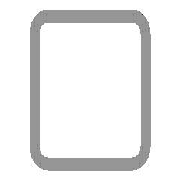
# Autodesk Inventor part: DIN EN 10219-2 - 90 x 90 x 5  - 120
Saved by Autodesk Inventor 2025.3 (Build 293356000, 356)
## iProperties
IsCustomPart: 1
Created: 2024-01-20
Part Number: DIN EN 10219-2 - 90 x 90 x 5  - 120
Material: Stahl, weich
Description: Kaltgeformte, geschweißte Baustahl-Hohlprofile aus unlegiertem Feinkorn-Baustahl
Document SubType Name: Modeling
Standard: DIN EN 10219-2
Designer: trist
Standard Revision: 2006-07
Standards Organization: DIN
Language: de-DE
Size Designation: 90 x 90 x 5  - 120
Categories: <MemberInstance><Categories><Category DisplayName="Profile" InternalName="089c4875-fa83-4c05-b084-43b9cc11f5ed" Mnemonic="GRDR"><CategoryParameter DisplayName="Masse pro Längeneinheit" InternalName="0bb95a10-148f-4027-a459-38d7b056702a" Mnemonic="shpmass"/><CategoryParameter DisplayName="Querschnittsfläche" InternalName="1ff91680-64b0-4202-b9a3-7fd3f94bba3b" Mnemonic="secarea"/><CategoryParameter DisplayName="Trägheitsradius (x)" InternalName="25778675-03e9-40c1-b6a8-4a9ed693320d" Mnemonic="gyrradx"/><CategoryParameter DisplayName="Torsion-Festigkeitsmodul" InternalName="26c1ec35-5026-4c63-ad0a-751cf684a536" Mnemonic="torrigmod"/><CategoryParameter DisplayName="Abstand zum Schwerpunkt X-X" InternalName="26c9bdb8-9c79-4b4f-a92e-8e197583c9c4" Mnemonic="grcendistX"/><CategoryParameter DisplayName="Alte Varianten-ID" InternalName="340afe4f-75d7-48d3-ab7d-943f3c3da468" Mnemonic="LegacyMemberID"/><CategoryParameter DisplayName="Basislänge" InternalName="42e34263-8f20-4d0e-ad48-bf1385b87c24" Mnemonic="shplen"/><CategoryParameter DisplayName="Trägheitsmoment (y)" InternalName="4b9f58ea-bced-460e-81ea-3d29ca5a49e3" Mnemonic="inermomy"/><CategoryParameter DisplayName="Trägheitsmoment (x)" InternalName="4cd780bc-73d7-43ac-917a-579e5cbd684d" Mnemonic="inermomx"/><CategoryParameter DisplayName="Benutzerdefinierter Basispunkt" InternalName="4f1d1b73-316d-484b-a3df-9cbabb16eb77" Mnemonic="shpBasePoint"/><CategoryParameter DisplayName="Objekthöhe" InternalName="50274e7d-5ac0-4796-92cb-c59e54983c67" Mnemonic="shpheig"/><CategoryParameter DisplayName="Widerstandsmoment (y)" InternalName="59eaa5e9-d227-48dc-b6c1-6920f96e0f95" Mnemonic="secmody"/><CategoryParameter DisplayName="Schnittbezeichnung" InternalName="5a64d034-428d-49c8-ba32-7619764de20f" Mnemonic="shpdes"/><CategoryParameter DisplayName="Widerstandsmoment (x)" InternalName="72cfad18-cf51-4ed4-aaa7-c6b224f8419f" Mnemonic="secmodx"/><CategoryParameter DisplayName="Drehrissmodul" InternalName="7c55a8dc-8844-49f9-a867-cc677b30ec9a" Mnemonic="torsecmod"/><CategoryParameter DisplayName="Objektbreite" InternalName="7c717d54-a18f-4666-b4d4-573cce22c62c" Mnemonic="shpwdth"/><CategoryParameter DisplayName="Zweite Objektdicke" InternalName="9251a8e1-85fd-4e47-af99-afdb762317d9" Mnemonic="shpthick2"/><CategoryParameter DisplayName="GG Erstellt" InternalName="9c666724-f362-4ea7-ac62-f6a007de5c69" Mnemonic="shpFGAuto"/><CategoryParameter DisplayName="Abstand zum Schwerpunkt Y-Y" InternalName="bcc4fb17-7af4-436a-8f8c-d0aa3b0248c5" Mnemonic="grcendistY"/><CategoryParameter DisplayName="Trägheitsradius (y)" InternalName="bfa18ebe-1636-4dbe-8d42-b263e0b73184" Mnemonic="gyrrady"/><CategoryParameter DisplayName="Objektdicke" InternalName="d109cf76-8eb4-42fc-9800-4409734adc67" Mnemonic="shpthick"/><CategoryParameter DisplayName="Koeffizient für Schubverschiebung" InternalName="de4c90c6-aaa8-468f-a335-6737b311b5d3" Mnemonic="shdispc"/><Category DisplayName="Vierkantrohre (quadratisch/rechteckig)" InternalName="afc8e2d8-05d6-4609-8807-f98a9b7d2ed0" Mnemonic="SQRSHP"><CategoryParameter DisplayName="Querschnittsfläche" InternalName="2f7f79dd-983c-4263-802a-5b6a1495fdc5" Mnemonic="secarea"/><CategoryParameter DisplayName="Widerstandsmoment (x)" InternalName="50d965a6-04bf-46b9-8ace-861858d348e6" Mnemonic="secmodx"/><CategoryParameter DisplayName="Widerstandsmoment (y)" InternalName="5106aeac-54a2-4159-a9af-8933dd39dba2" Mnemonic="secmody"/><CategoryParameter DisplayName="Objektdicke" InternalName="52712fc5-f4ee-4eda-b3f2-6fce82c26419" Mnemonic="shpthick"/><CategoryParameter DisplayName="Trägheitsmoment (y)" InternalName="55ec8510-8276-4c45-8f10-594e0fee7eb3" Mnemonic="inermomy"/><CategoryParameter DisplayName="Trägheitsradius (x)" InternalName="56c89926-a299-4389-a862-ac94c9691272" Mnemonic="gyrradx"/><CategoryParameter DisplayName="Radius" InternalName="5d8d062c-e28e-41c1-98da-8e5fee36da1a" Mnemonic="shprad"/><CategoryParameter DisplayName="Trägheitsmoment (x)" InternalName="8c4637b6-6b69-4878-9d5d-26a32185d655" Mnemonic="inermomx"/><CategoryParameter DisplayName="Objektbreite" InternalName="8c8a1782-5e80-4d77-858b-304b1c0ad1fd" Mnemonic="shpwdth"/><CategoryParameter DisplayName="Trägheitsradius (y)" InternalName="fa48a7f5-f030-40f9-a60b-de8a845b7104" Mnemonic="gyrrady"/></Category></Category><Category DisplayName="Datentyp" InternalName="23b78d0f-2648-40c6-8793-ca6db495c9e8" Mnemonic="DATATYPE"><CategoryParameter DisplayName="Anzeigename" InternalName="05415f3d-3907-474b-a020-eb9d644f4cf3" Mnemonic="DISPLAYNAME"/><CategoryParameter DisplayName="Norm" InternalName="0c0a119c-1e12-4c84-803f-101930972f5e" Mnemonic="STANDARD"/><CategoryParameter DisplayName="Beschreibung" InternalName="13903e3d-64b1-4950-80da-f627842ea37f" Mnemonic="DESCRIPTION"/><CategoryParameter DisplayName="Bezeichnung" InternalName="2675968c-4ce5-49e0-a4f5-552d29089031" Mnemonic="DESIGNATION"/><CategoryParameter DisplayName="Standardzeile" InternalName="2af9ec52-faaa-4026-b378-f9fa4afca842" Mnemonic="DEFAULTROW"/><CategoryParameter DisplayName="Ordnername" InternalName="3f06958e-8713-4116-9be7-ed6184ecc97b" Mnemonic="FOLDERNAME"/><CategoryParameter DisplayName="Revisionsanleitung" InternalName="45a75005-10b1-4dfc-8d6d-dfe629f0b93c" Mnemonic="REVISIONGUID"/><CategoryParameter DisplayName="Dateiname" InternalName="8b46a4cc-9585-4fed-90c3-899f57e09a73" Mnemonic="FILENAME"/><CategoryParameter DisplayName="Normungsorganisation" InternalName="8f5914e1-4693-403f-8ab5-d37768198c9d" Mnemonic="STDSORG"/><CategoryParameter DisplayName="Gruppenversion" InternalName="914462f6-6e19-4b14-ba84-155b9680b1d0" Mnemonic="FAMILYREVISION"/><CategoryParameter DisplayName="Normrevision" InternalName="91d5a463-65c2-4fde-b823-3b7fea5e8e17" Mnemonic="STANDARDREVISION"/><CategoryParameter DisplayName="Variantenrevision" InternalName="a65d44b9-392f-4f4f-857b-e4b3d54996fe" Mnemonic="MEMBERREVISION"/><CategoryParameter DisplayName="ClipFormat" InternalName="bc51e27b-3422-4e78-93ef-cec197ddf230" Mnemonic="CLIPFORMAT"/><CategoryParameter DisplayName="Hersteller" InternalName="cd6c7a72-a28a-4e50-99a9-2c7f4e13e5ad" Mnemonic="MANUFACTURER"/><CategoryParameter DisplayName="InternerName" InternalName="cf1d0246-76d9-4b4a-8305-fa0409afb5c1" Mnemonic="INTERNALNAME"/><CategoryParameter DisplayName="IstMetrisch" InternalName="e2385c5b-1ea4-4823-96a8-8de651266ec3" Mnemonic="ISMETRIC"/><Category DisplayName="Bauteil" InternalName="c0e0b642-3bcb-4cc8-9e80-f96d35c4afa4" Mnemonic="PART"><CategoryParameter DisplayName="Bauteilnummer" InternalName="016b6077-bfbe-49bd-92c9-d8d59c39c941" Mnemonic="PARTNUMBER"/><CategoryParameter DisplayName="Bestandsnummer" InternalName="4dba7c1c-e26c-444e-836c-b08b433409a8" Mnemonic="STOCKNUMBER"/><CategoryParameter DisplayName="Materialschlüssel" InternalName="5c9a8adb-dd2b-4535-b97f-0a94a95fe41f" Mnemonic="MATERIALKEY"/><CategoryParameter DisplayName="Material" InternalName="818a152a-d3c3-49ca-80ee-df7d91421b8e" Mnemonic="MATERIAL"/></Category></Category><Category DisplayName="ÄltereVersionenzuweisen" InternalName="cd87c42b-3e48-431e-b5c0-1cbeb14dfe77" Mnemonic="LEGACYMAP"><CategoryParameter DisplayName="Eindeutige DA-Varianten-ID" InternalName="0918ad47-427f-4fed-ae26-24c81c58f590" Mnemonic="DACOOKIE"/><CategoryParameter DisplayName="ID zusammenführen" InternalName="0ee8fb18-e2ed-4f39-96f6-1f4b5f50aa71" Mnemonic="MERGE11"/><CategoryParameter DisplayName="Eindeutige CC-Varianten-ID" InternalName="5193edd4-b2b0-4ab4-9d54-de900eee34e0" Mnemonic="CCCOOKIE"/><CategoryParameter DisplayName="ID aufteilen" InternalName="72b5c83c-be7f-45c4-ae51-9160ea6deb26" Mnemonic="SPLIT"/><CategoryParameter DisplayName="VarianteID" InternalName="8e5e0294-fc51-4c8f-b3d7-003dc5ed94f6" Mnemonic="MEMBERID"/><CategoryParameter DisplayName="Katalogname" InternalName="d99d1e27-aa94-4de2-af4c-c348882a6f4f" Mnemonic="CATALOGNAME"/><CategoryParameter DisplayName="Gruppennummer" InternalName="e705e1f4-09cb-413e-91f9-551b4188271e" Mnemonic="FAMILYNUMBER"/></Category></Categories><FamilyTemplate Id="gp0601"><FamilyTemplateParameters><FamilyTemplateParameter ObjectType="kUserParameterObject" ValueType="xs:double" Id="1" ObjectReferenceKey="G_H"/><FamilyTemplateParameter ObjectType="kUserParameterObject" ValueType="xs:double" Id="2" ObjectReferenceKey="B_L"/><FamilyTemplateParameter ObjectType="kUserParameterObject" ValueType="xs:double" Id="6" ObjectReferenceKey="G_W"/><FamilyTemplateParameter ObjectType="kUserParameterObject" ValueType="xs:double" Id="7" ObjectReferenceKey="G_T"/><FamilyTemplateParameter ObjectType="kUserParameterObject" ValueType="xs:double" Id="8" ObjectReferenceKey="G_IR"/><FamilyTemplateParameter ObjectType="kPropertyObject" ValueType="xs:string" Id="100" ObjectReferenceKey="{32853F0F-3444-11d1-9E93-0060B03C1CA6}" SubObjectId="52"/><FamilyTemplateParameter ObjectType="kPropertyObject" ValueType="xs:string" Id="105" ObjectReferenceKey="{32853F0F-3444-11d1-9E93-0060B03C1CA6}" SubObjectId="5"/><FamilyTemplateParameter ObjectType="kPartComponentDefinitionObject" ValueType="xs:string" Id="110" SubObjectId="Material"/><FamilyTemplateParameter ObjectType="kPropertyObject" ValueType="xs:string" Id="112" ObjectReferenceKey="{32853F0F-3444-11d1-9E93-0060B03C1CA6}" SubObjectId="55"/></FamilyTemplateParameters></FamilyTemplate><CategoryParameterMap><ParamToTemplateMap><ParamToTemplate CategoryParameter="//CategoryParameter[@InternalName='05415f3d-3907-474b-a020-eb9d644f4cf3']" ConstantValue="DIN EN 10219-2 (Square Hollow Section - Cold Formed)"/><ParamToTemplate CategoryParameter="//CategoryParameter[@InternalName='cf1d0246-76d9-4b4a-8305-fa0409afb5c1']" ConstantValue="f4eb4807-7530-48bf-9740-f5a60eee53a8"/><ParamToTemplate CategoryParameter="//CategoryParameter[@InternalName='3f06958e-8713-4116-9be7-ed6184ecc97b']" ConstantValue="DIN EN 10219-2(1)"/><ParamToTemplate CategoryParameter="//CategoryParameter[@InternalName='914462f6-6e19-4b14-ba84-155b9680b1d0']" ConstantValue="10"/><ParamToTemplate CategoryParameter="//CategoryParameter[@InternalName='bc51e27b-3422-4e78-93ef-cec197ddf230']" ConstantValue="CF_INVENTOR.STDPARTS"/><ParamToTemplate CategoryParameter="//CategoryParameter[@InternalName='e2385c5b-1ea4-4823-96a8-8de651266ec3']" ConstantValue="true"/><ParamToTemplate CategoryParameter="//CategoryParameter[@InternalName='13903e3d-64b1-4950-80da-f627842ea37f']" ConstantValue="Cold formed welded structural hollow sections of non-alloy and fine grain structural steel"/><ParamToTemplate CategoryParameter="//CategoryParameter[@InternalName='8f5914e1-4693-403f-8ab5-d37768198c9d']" ConstantValue="DIN"/><ParamToTemplate CategoryParameter="//CategoryParameter[@InternalName='0c0a119c-1e12-4c84-803f-101930972f5e']" ConstantValue="DIN EN 10219-2"/><ParamToTemplate CategoryParameter="//CategoryParameter[@InternalName='cd6c7a72-a28a-4e50-99a9-2c7f4e13e5ad']" TemplateParameter="104"/><ParamToTemplate CategoryParameter="//CategoryParameter[@InternalName='91d5a463-65c2-4fde-b823-3b7fea5e8e17']" ConstantValue="2006-07"/><ParamToTemplate CategoryParameter="//CategoryParameter[@InternalName='45a75005-10b1-4dfc-8d6d-dfe629f0b93c']" ConstantValue="fa0180ad-9900-4c48-9c99-ee51de72b725"/><ParamToTemplate CategoryParameter="//CategoryParameter[@InternalName='2af9ec52-faaa-4026-b378-f9fa4afca842']" ConstantValue="1"/><ParamToTemplate CategoryParameter="//CategoryParameter[@InternalName='9c666724-f362-4ea7-ac62-f6a007de5c69']" ConstantValue="1"/><ParamToTemplate CategoryParameter="//CategoryParameter[@InternalName='d99d1e27-aa94-4de2-af4c-c348882a6f4f']" ConstantValue="BSI"/><ParamToTemplate CategoryParameter="//CategoryParameter[@InternalName='e705e1f4-09cb-413e-91f9-551b4188271e']" ConstantValue="158"/><ParamToTemplate CategoryParameter="//CategoryParameter[@InternalName='8b46a4cc-9585-4fed-90c3-899f57e09a73']" ConstantValue="DIN EN 10219-2 - 90 x 90 x 5  - 120"/><ParamToTemplate CategoryParameter="//CategoryParameter[@InternalName='a65d44b9-392f-4f4f-857b-e4b3d54996fe']" ConstantValue="49229FD5-5431-4EE6-B6F3-2C28CB392A87"/><ParamToTemplate CategoryParameter="//CategoryParameter[@InternalName='8c4637b6-6b69-4878-9d5d-26a32185d655']" ConstantValue="193"/><ParamToTemplate CategoryParameter="//CategoryParameter[@InternalName='56c89926-a299-4389-a862-ac94c9691272']" ConstantValue="34,3"/><ParamToTemplate CategoryParameter="//CategoryParameter[@InternalName='50d965a6-04bf-46b9-8ace-861858d348e6']" ConstantValue="42,9"/><ParamToTemplate CategoryParameter="//CategoryParameter[@InternalName='2f7f79dd-983c-4263-802a-5b6a1495fdc5']" ConstantValue="16,4"/><ParamToTemplate CategoryParameter="//CategoryParameter[@InternalName='7c55a8dc-8844-49f9-a867-cc677b30ec9a']" ConstantValue="64,7"/><ParamToTemplate CategoryParameter="//CategoryParameter[@InternalName='26c1ec35-5026-4c63-ad0a-751cf684a536']" ConstantValue="316"/><ParamToTemplate CategoryParameter="//CategoryParameter[@InternalName='de4c90c6-aaa8-468f-a335-6737b311b5d3']" ConstantValue="2,1962593"/><ParamToTemplate CategoryParameter="//CategoryParameter[@InternalName='5a64d034-428d-49c8-ba32-7619764de20f']" ConstantValue="90 x 90 x 5"/><ParamToTemplate CategoryParameter="//CategoryParameter[@InternalName='8e5e0294-fc51-4c8f-b3d7-003dc5ed94f6']" ConstantValue="38"/><ParamToTemplate CategoryParameter="//CategoryParameter[@InternalName='42e34263-8f20-4d0e-ad48-bf1385b87c24']" TemplateParameter="2"/><ParamToTemplate CategoryParameter="//CategoryParameter[@InternalName='2675968c-4ce5-49e0-a4f5-552d29089031']" TemplateParameter="100"/><ParamToTemplate CategoryParameter="//CategoryParameter[@InternalName='50274e7d-5ac0-4796-92cb-c59e54983c67']" TemplateParameter="1"/><ParamToTemplate CategoryParameter="//CategoryParameter[@InternalName='52712fc5-f4ee-4eda-b3f2-6fce82c26419']" TemplateParameter="7"/><ParamToTemplate CategoryParameter="//CategoryParameter[@InternalName='8c8a1782-5e80-4d77-858b-304b1c0ad1fd']" TemplateParameter="6"/><ParamToTemplate CategoryParameter="//CategoryParameter[@InternalName='818a152a-d3c3-49ca-80ee-df7d91421b8e']" TemplateParameter="110"/><ParamToTemplate CategoryParameter="//CategoryParameter[@InternalName='016b6077-bfbe-49bd-92c9-d8d59c39c941']" TemplateParameter="105"/><ParamToTemplate CategoryParameter="//CategoryParameter[@InternalName='4dba7c1c-e26c-444e-836c-b08b433409a8']" TemplateParameter="112"/></ParamToTemplateMap></CategoryParameterMap></MemberInstance>
Stock Number: 90 x 90 x 5
Mass: 1529.59 g
Surface Area: 812.069 cm^2
Volume: 194.852 cm^3
Density: 7.85 g/cm^3
Appearance: Halbpoliert
G_L: 120,000 mm
Author: trist
Autodesk Inventor part; units mm, degrees
ref_plane "YZ Plane" through (0, 0, 0) normal (1, 0, 0) x (0, 1, 0)
ref_plane "Startebene" through (0, 0, 0) normal (0, 0, 1) x (1, 0, 0)
ref_plane "Endebene" through (0, 0, 120) normal (0, 0, 1) x (1, 0, 0)
sketch "Skizze" plane through (0, 0, 0) normal (0, 0, 1) x (1, 0, 0)
  line L0 (-45, -35) -> (-45, 35)
  line L1 (-35, 45) -> (35, 45)
  line L2 (45, 35) -> (45, -35)
  line L3 (35, -45) -> (-35, -45)
  arc A0 (-45, -35) -> (-35, -45) centre (-35, -35) ccw
  arc A1 (-35, 45) -> (-45, 35) centre (-35, 35) ccw
  arc A2 (45, 35) -> (35, 45) centre (35, 35) ccw
  arc A3 (35, -45) -> (45, -35) centre (35, -35) ccw
  arc A4 (-35, 40) -> (-40, 35) centre (-35, 35) ccw
  line L4 (-35, 40) -> (35, 40)
  arc A5 (40, 35) -> (35, 40) centre (35, 35) ccw
  line L5 (40, 35) -> (40, -35)
  arc A6 (35, -40) -> (40, -35) centre (35, -35) ccw
  line L6 (35, -40) -> (-35, -40)
  arc A7 (-40, -35) -> (-35, -40) centre (-35, -35) ccw
  line L7 (-40, -35) -> (-40, 35)
  line L8 (0, 65.8995) -> (0, -65.8995) construction
  line L9 (-65.8995, 0) -> (65.8995, 0) construction
  dimension "d7" = 10
  dimension "d10" = 90
  dimension "d11" = 90
  dimension "d12" = 5
  dimension "d15" = 45
  dimension "d16" = 45
  constraints: 16 end point, 16 point on circle, 8 centre point, 8 tangent, 4 parallel, 3 equal radius, 2 perpendicular, 7 other
  measures "d7" radius of A0
  measures "d10" distance between parallel lines of L1 L3
  measures "d11" distance between parallel lines of L0 L2
  measures "d12" distance between parallel lines of L2 L5
  measures "d15" distance between parallel lines of L1 L9
  measures "d16" distance between parallel lines of L8 L2
extrude "Körper" add sketch "Skizze" along normal up to surface (120 mm away) from surface at 0
sketch "Sketch3" plane through (0, 0, 0) normal (0, 0, 1) x (1, 0, 0)
  line L0 (0, 0) -> (10, 0)
ref_plane "Work Plane3" through (0, 0, 0) normal (0, -1, 0) x (1, 0, 0)
sketch "Skizze5" plane through (-35, -45, 0) normal (0, -1, 0) x (1, 0, 0)
  line L0 (18, 62) -> (63, 62)
  line L1 (63, 62) -> (63, 120)
  line L2 (63, 120) -> (18, 120)
  line L3 (18, 120) -> (18, 62)
  line L4 (70, 120) -> (0, 120) projected
  line L5 (0, 120) -> (70, 120)
  line L6 (70, 0) -> (70, 120) projected
  line L7 (0, 0) -> (0, 120) projected
  point P0 (35, 0)
  point P1 (35, 120)
  dimension "d19" = 58
  dimension "d20" = 0
  dimension "d21" = 45
  dimension "d99" = 63
  constraints: 10 end point, 2 horizontal, 2 parallel, 1 midpoint, 1 perpendicular
  measures "d19" distance between parallel lines of L0 L4
  measures "d20" distance between parallel lines of L4 L2
  measures "d21" distance between parallel lines of L1 L3
  measures "d99" distance between parallel lines of L1 L7
extrude "Extrusion2" cut sketch "Skizze5" against normal blind 10
sketch "Skizze6" plane through (0, 0, 0) normal (0, 0, -1) x (-1, 0, 0)
  line L0 (63, 0) -> (-63, 0) projected
  line L1 (0, -63) -> (0, 63) projected
  line L2 (-40, -35) -> (-40, 35) projected
  line L3 (-35, 40) -> (35, 40) projected
  line L4 (40, 35) -> (40, -35) projected
  line L5 (35, -40) -> (-35, -40) projected
  circle A0 centre (-31.82, 31.82) radius 3
  circle A1 centre (-31.82, -31.82) radius 3
  circle A2 centre (31.82, -31.82) radius 3
  circle A3 centre (31.82, 31.82) radius 3
  line L6 (-40, 40) -> (-26, 40)
  line L7 (-26, 40) -> (-26, 26)
  line L8 (-26, 26) -> (-40, 26)
  line L9 (-40, 26) -> (-40, 40)
  line L10 (-40, -40) -> (-26, -40)
  line L11 (-26, -40) -> (-26, -26)
  line L12 (-26, -26) -> (-40, -26)
  line L13 (-40, -26) -> (-40, -40)
  line L14 (40, -40) -> (26, -40)
  line L15 (26, -40) -> (26, -26)
  line L16 (26, -26) -> (40, -26)
  line L17 (40, -26) -> (40, -40)
  line L18 (40, 40) -> (26, 40)
  line L19 (26, 40) -> (26, 26)
  line L20 (26, 26) -> (40, 26)
  line L21 (40, 26) -> (40, 40)
  point P0 (0, 0)
  point P1 (-28, -26)
  point P2 (-26, -28)
  point P3 (-28, 26)
  point P4 (-26, 28)
  point P5 (26, 28)
  point P6 (28, 26)
  point P7 (26, -28)
  point P8 (28, -26)
  point P9 (-35, -40)
  dimension "d110" = 6
  dimension "d28" = 6
  dimension "d29" = 6
  dimension "d30" = 6
  dimension "d31" = 6
  dimension "d32" = 63.64
  dimension "d33" = 63.64
  dimension "d34" = 63.64
  dimension "d36" = 63.64
  dimension "d37" = 8.18
  dimension "d38" = 8.18
  dimension "d39" = 8.18
  dimension "d40" = 8.18
  dimension "d41" = 14
  dimension "d42" = 14
  dimension "d43" = 14
  dimension "d44" = 14
  dimension "d45" = 14
  dimension "d46" = 14
  dimension "d47" = 14
  dimension "d48" = 14
  dimension "d49" = 52
  dimension "d50" = 52
  dimension "d51" = 52
  dimension "d52" = 52
  dimension "d54" = 2
  dimension "d55" = 2
  dimension "d56" = 2
  dimension "d57" = 2
  dimension "d58" = 2
  dimension "d59" = 2
  dimension "d60" = 2
  dimension "d61" = 2
  constraints: 32 end point, 10 point on line, 8 parallel, 4 centre point, 4 horizontal, 4 perpendicular, 2 other
  measures "d28" diameter of A1
  measures "d29" diameter of A2
  measures "d30" diameter of A3
  measures "d31" diameter of A0
  measures "d32" distance of A3.centre A0.centre
  measures "d33" distance of A1.centre A0.centre
  measures "d34" distance of A2.centre A1.centre
  measures "d36" distance of A2.centre A3.centre
  measures "d37" distance from line of L3 A0.centre
  measures "d38" distance from line of L2 A1.centre
  measures "d39" distance from line of L5 A2.centre
  measures "d40" distance from line of L4 A3.centre
  measures "d41" distance of L7.end L8.end
  measures "d42" distance of L6.end L7.end
  measures "d43" distance of L12.end L11.end
  measures "d44" distance of L11.end L10.end
  measures "d45" distance of L15.end L16.end
  measures "d46" distance of L14.end L15.end
  measures "d47" distance of L20.end L19.end
  measures "d48" distance of L19.end L18.end
  measures "d49" distance between parallel lines of L12 L8
  measures "d50" distance between parallel lines of L15 L11
  measures "d51" distance between parallel lines of L20 L16
  measures "d52" distance between parallel lines of L7 L19
  measures "d54" distance from line of point (-28, -26) L11
  measures "d55" distance from line of L12 point (-26, -28)
  measures "d56" distance from line of L7 point (-28, 26)
  measures "d57" distance from line of L8 point (-26, 28)
  measures "d58" distance from line of L20 point (26, 28)
  measures "d59" distance from line of L19 point (28, 26)
  measures "d60" distance from line of L15 point (28, -26)
  measures "d61" distance from line of L16 point (26, -28)
extrude "Extrusion3" add sketch "Skizze6" against normal blind 18 contours L20 L19 L3 L18 L21 L4 | L4 L17 L14 L5 L15 L16 | L12 L11 L5 L10 L13 L2 | L2 L9 L6 L3 L7 L8
fillet "Rundung3" radius 2 4 edges at (26, 26, 9) (26, -26, 9) (-26, 26, 9) (-26, -26, 9)
sketch "Skizze7" plane through (0, 0, 0) normal (0, 0, -1) x (-1, 0, 0)
  line L0 (63, 0) -> (-63, 0) projected
  line L1 (0, -63) -> (0, 63) projected
  arc A0 (-35, 40) -> (-40, 35) centre (-35, 35) ccw
  line L2 (-35, 40) -> (35, 40)
  arc A1 (40, 35) -> (35, 40) centre (35, 35) ccw
  line L3 (40, 35) -> (40, -35)
  arc A2 (35, -40) -> (40, -35) centre (35, -35) ccw
  line L4 (35, -40) -> (-35, -40)
  arc A3 (-40, -35) -> (-35, -40) centre (-35, -35) ccw
  line L5 (-40, -35) -> (-40, 35)
  line L6 (-40, 25.2444) -> (-24.3023, 25.2444)
  line L7 (-24.3023, 25.2444) -> (-24.3023, 40)
  line L8 (22.4189, 40) -> (22.4189, 25.2444)
  line L9 (22.4189, 25.2444) -> (40, 25.2444)
  line L10 (40, -23.7043) -> (24.0553, -23.7043)
  line L11 (24.0553, -23.7043) -> (24.0553, -40)
  line L12 (-24.3023, -40) -> (-24.3023, -23.1999)
  line L13 (-24.3023, -23.1999) -> (-40, -23.1999)
  point P0 (32.0277, -23.7043)
  dimension "d77" = 5
  dimension "d78" = 70
  dimension "d80" = 5
  dimension "d81" = 70
  dimension "d82" = 5
  dimension "d83" = 70
  dimension "d84" = 5
  dimension "d85" = 48.4444
  dimension "d86" = 46.7212
  dimension "d87" = 48.9488
  dimension "d88" = 48.3576
  dimension "d89" = 25.2444
  dimension "d90" = 24.3023
  constraints: 24 end point, 12 point on line, 8 point on circle, 4 centre point, 4 horizontal, 3 perpendicular, 2 vertical, 1 midpoint, 1 parallel
  measures "d77" radius of A0
  measures "d78" distance of L2.start L2.end
  measures "d80" radius of A1
  measures "d81" distance of L3.start L3.end
  measures "d82" radius of A2
  measures "d83" distance of L4.start L4.end
  measures "d84" radius of A3
  measures "d85" distance between parallel lines of L13 L6
  measures "d86" distance between parallel lines of L8 L7
  measures "d87" distance from line of point (32.028, -23.704) L9
  measures "d88" distance between parallel lines of L12 L11
  measures "d89" distance between parallel lines of L0 L6
  measures "d90" distance between parallel lines of L1 L7
extrude "Extrusion4" cut sketch "Skizze7" against normal blind 8 contours L9 L8 L2 A1 L3 | L3 A2 L4 L11 L10 | L13 L12 L4 A3 L5 | L5 A0 L2 L7 L6
sketch "Skizze8" plane through (-35, 40, 120) normal (0, 0, 1) x (1, 0, 0)
  line L0 (35, -103) -> (35, 23) projected
  line L1 (-28, -40) -> (98, -40) projected
  line L2 (-5, -5) -> (-5, -75) projected
  line L3 (70, 0) -> (0, 0) projected
  line L4 (75, -75) -> (75, -5) projected
  line L5 (0, -80) -> (18, -80) projected
  line L6 (18, -80) -> (63, -80) projected
  line L7 (63, -80) -> (70, -80) projected
  line L8 (-5, 0) -> (9, 0)
  line L9 (9, 0) -> (9, -14)
  line L10 (9, -14) -> (-5, -14)
  line L11 (-5, -14) -> (-5, 0)
  line L12 (75, 0) -> (61, 0)
  line L13 (61, 0) -> (61, -14)
  line L14 (61, -14) -> (75, -14)
  line L15 (75, -14) -> (75, 0)
  line L16 (75, -80) -> (61, -80)
  line L17 (61, -80) -> (61, -66)
  line L18 (61, -66) -> (75, -66)
  line L19 (75, -66) -> (75, -80)
  line L20 (-5, -80) -> (9, -80)
  line L21 (9, -80) -> (9, -66)
  line L22 (9, -66) -> (-5, -66)
  line L23 (-5, -66) -> (-5, -80)
  circle A0 centre (3.18, -8.18) radius 3 projected
  circle A1 centre (3.18, -8.18) radius 3
  circle A2 centre (66.82, -71.82) radius 3 projected
  circle A3 centre (66.82, -71.82) radius 3
  circle A4 centre (66.82, -8.18) radius 3
  circle A5 centre (3.18, -71.82) radius 3 projected
  circle A6 centre (3.18, -71.82) radius 3
  point P0 (-5, -14)
  point P1 (0, -80)
  point P2 (9, -80)
  point P3 (-5, -66)
  point P4 (75, -66)
  point P5 (61, 0)
  point P6 (75, -14)
  point P7 (-5, -14)
  point P8 (9, 0)
  dimension "d100" = 14
  dimension "d101" = 14
  dimension "d102" = 14
  dimension "d103" = 14
  dimension "d104" = 14
  dimension "d105" = 14
  dimension "d106" = 14
  dimension "d107" = 14
  dimension "d108" = 6
  dimension "d109" = 6
  dimension "d110" = 6
  constraints: 32 end point, 8 parallel, 4 centre point, 4 horizontal, 4 perpendicular, 3 coincident, 1 concentric, 1 point on line
  measures "d100" distance of L9.end L10.end
  measures "d101" distance of L8.end L9.end
  measures "d102" distance of L14.end L13.end
  measures "d103" distance of L13.end L12.end
  measures "d104" distance of L17.end L18.end
  measures "d105" distance of L16.end L17.end
  measures "d106" distance of L22.end L21.end
  measures "d107" distance of L21.end L20.end
  measures "d108" diameter of A3
  measures "d109" diameter of A4
  measures "d110" diameter of A6
extrude "Extrusion5" add sketch "Skizze8" against normal blind 8 contours L17 L18 L4 L19 L16 L7 L6 | L5 L20 L23 L2 L22 L21 | L3 L12 L15 L4 L14 L13 | L9 L10 L2 L11 L8 L3
fillet "Rundung4" radius 2 4 edges at (-26, 26, 116) (-26, -26, 116) (26, 26, 116) (26, -26, 116)
sketch "Sketch4" plane through (0, 0, 0) normal (0, -1, 0) x (1, 0, 0)
  line L0 (-2, 0) -> (12, 0) projected
  line L1 (-2, 120) -> (12, 120) projected
  dimension "d18" = 120
  measures "d18" distance between parallel lines of L0 L1
equation "\"d7\" = G_IR"
equation "\"d10\" = G_H"
equation "\"d11\" = G_W"
equation "\"d12\" = G_T"
equation "\"d15\" = 0.5 * d10"
equation "\"d16\" = 0.5 * d11"
equation "\"d3\" = G_L"
equation "\"G_W\" = 90"
equation "\"G_H\" = 90"
equation "\"G_T\" = 5"
equation "\"G_IR\" = 10"
equation "\"G_L\" = d18"
equation "\"G_OFFSET_START\" = 0"
equation "\"G_OFFSET_END\" = 0"
body "Solid1"
